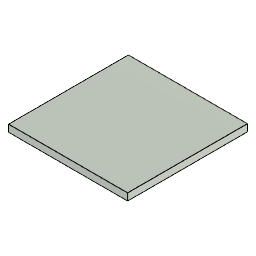
ZAxis (Autodesk Fusion 360 archive; units mm, degrees)
design "plate"
Autodesk Fusion 360 part; units mm, degrees
sketch "Sketch1" plane through (0, 0, 0) normal (0, 0, 1) x (1, 0, 0)
  line L0 (70.0675, 75.402) -> (-70.0675, 75.402)
  line L1 (-70.0675, 75.402) -> (-70.0675, -75.402)
  line L2 (-70.0675, -75.402) -> (70.0675, -75.402)
  line L3 (70.0675, -75.402) -> (70.0675, 75.402)
  line L4 (70.0675, 75.402) -> (-70.0675, -75.402) construction
  line L5 (-70.0675, 75.402) -> (70.0675, -75.402) construction
  constraint horizontal L0
  constraint perpendicular L0 L1
  constraint parallel L0 L2
  constraint parallel L1 L3
  constraint coincident L4 origin
  constraint coincident L5 origin
extrude "Extrude1" add sketch "Sketch1" along normal blind 6
move_face "OffsetFaces1" offset -45 1 faces at (70.0675, -25.134, 2)
move_face "OffsetFaces2" offset 5 1 faces at (-70.0675, -25.134, 4)
move_face "OffsetFaces3" offset -50 1 faces at (-8.3108, -75.402, 4)
